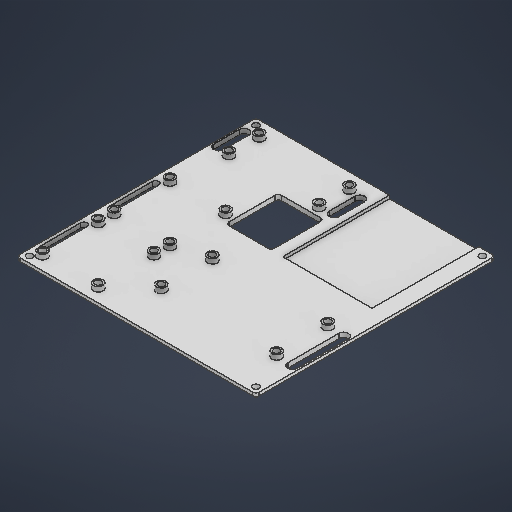
# Autodesk Inventor part: Control Board
Saved by Autodesk Inventor 2026.2 (Build 302298010, 298A)
## iProperties
Created: 2026-04-28
Part Number: Control Board
Material: 일반
Document SubType Name: Modeling
Designer: work
Density: 1 g/cm^3
Appearance: 기본값
Author: work
Autodesk Inventor part; units mm, degrees
ref_plane "YZ Plane" through (0, 0, 0) normal (1, 0, 0) x (0, 1, 0)
ref_plane "XZ Plane" through (0, 0, 0) normal (0, 1, 0) x (-1, 0, 0)
ref_plane "XY Plane" through (0, 0, 0) normal (0, 0, 1) x (1, 0, 0)
sketch "스케치1" plane through (0, 0, 0) normal (0, 1, 0) x (-1, 0, 0)
  line L0 (150, -150) -> (0, -150)
  line L1 (0, -150) -> (0, 0)
  line L2 (0, 0) -> (150, 0)
  line L3 (150, 0) -> (150, -150)
  line L4 (150, -150) -> (0, 0) construction
  line L5 (0, -150) -> (150, 0) construction
  line L6 (4, -4) -> (146, -4) construction
  line L7 (146, -4) -> (146, -146) construction
  line L8 (146, -146) -> (4, -146) construction
  line L9 (4, -146) -> (4, -4) construction
  line L10 (4, -4) -> (146, -146) construction
  line L11 (146, -4) -> (4, -146) construction
  circle A0 centre (146, -4) radius 2
  circle A1 centre (146, -146) radius 2
  circle A2 centre (4, -4) radius 2
  circle A3 centre (4, -146) radius 2
  line L12 (14, -27) -> (86.4, -27) construction
  line L13 (86.4, -27) -> (86.4, -59) construction
  line L14 (86.4, -59) -> (14, -59) construction
  line L15 (14, -59) -> (14, -27) construction
  line L16 (86.4, -43) -> (14, -43) construction
  line L17 (50.2, -27) -> (50.2, -59) construction
  line L18 (10.2, -8) -> (90.2, -8) construction
  line L19 (90.2, -8) -> (90.2, -78) construction
  line L20 (90.2, -78) -> (10.2, -78) construction
  line L21 (10.2, -78) -> (10.2, -8) construction
  line L22 (10.2, -8) -> (90.2, -78) construction
  line L23 (90.2, -8) -> (10.2, -78) construction
  circle A4 centre (14, -27) radius 2
  circle A5 centre (14, -59) radius 2
  circle A6 centre (86.4, -27) radius 2
  circle A7 centre (86.4, -59) radius 2
  line L24 (4, -27) -> (4, -59) construction
  line L25 (1, -27) -> (1, -59)
  line L26 (7, -59) -> (7, -27)
  arc A8 (7, -27) -> (1, -27) centre (4, -27) ccw
  arc A9 (1, -59) -> (7, -59) centre (4, -59) ccw
  line L27 (4, -43) -> (14, -43) construction
  line L28 (10.2, -88) -> (10.2, -78) construction
  circle A10 centre (142, -43) radius 2
  line L29 (142, -8) -> (142, -43) construction
  circle A11 centre (142, -8) radius 2
  line L30 (142, -43) -> (107, -43) construction
  circle A12 centre (107, -43) radius 2
  line L31 (107, -43) -> (107, -8) construction
  line L32 (107, -8) -> (142, -43) construction
  line L33 (142, -8) -> (107, -43) construction
  line L34 (107, -8) -> (142, -8) construction
  circle A13 centre (107, -8) radius 2
  circle A14 centre (142, -88) radius 2
  line L35 (142, -53) -> (142, -88) construction
  circle A15 centre (142, -53) radius 2
  line L36 (142, -88) -> (107, -88) construction
  circle A16 centre (107, -88) radius 2
  line L37 (107, -88) -> (107, -53) construction
  line L38 (107, -53) -> (142, -88) construction
  line L39 (142, -53) -> (107, -88) construction
  line L40 (107, -53) -> (142, -53) construction
  circle A17 centre (107, -53) radius 2
  line L41 (138, -140) -> (81.4, -140) construction
  line L42 (81.4, -140) -> (81.4, -121) construction
  line L43 (81.4, -121) -> (138, -121) construction
  line L44 (138, -121) -> (138, -140) construction
  line L45 (138, -140) -> (81.4, -121) construction
  line L46 (81.4, -140) -> (138, -121) construction
  circle A18 centre (81.4, -121) radius 2
  circle A19 centre (81.4, -140) radius 2
  circle A20 centre (138, -121) radius 2
  circle A21 centre (138, -140) radius 2
  line L47 (73.4, -138.5) -> (73.4, -122.5) construction
  line L48 (76.4, -138.5) -> (76.4, -122.5)
  arc A22 (70.4, -138.5) -> (76.4, -138.5) centre (73.4, -138.5) ccw
  arc A23 (76.4, -122.5) -> (70.4, -122.5) centre (73.4, -122.5) ccw
  line L49 (109.7, -121) -> (109.7, -140) construction
  line L50 (109.7, -130.5) -> (73.4, -130.5) construction
  arc A24 (143, -138.5) -> (149, -138.5) centre (146, -138.5) ccw
  line L51 (143, -138.5) -> (143, -122.5)
  arc A25 (149, -122.5) -> (143, -122.5) centre (146, -122.5) ccw
  line L52 (109.7, -130.5) -> (146, -130.5) construction
  line L53 (146, -138.5) -> (146, -122.5) construction
  line L54 (70.4, -122.5) -> (70.4, -138.5)
  line L55 (149, -122.5) -> (149, -138.5)
  line L56 (66.2, -83) -> (10.2, -83)
  line L57 (10.2, -83) -> (10.2, -166)
  line L58 (10.2, -166) -> (66.2, -166)
  line L59 (66.2, -166) -> (66.2, -83)
  line L60 (102, -83) -> (73.4, -83)
  line L61 (73.4, -83) -> (73.4, -116)
  line L62 (73.4, -116) -> (102, -116)
  line L63 (102, -116) -> (102, -83)
  line L64 (146, -13) -> (146, -38) construction
  line L65 (144, -13) -> (144, -38)
  line L66 (148, -38) -> (148, -13)
  arc A26 (148, -13) -> (144, -13) centre (146, -13) ccw
  arc A27 (144, -38) -> (148, -38) centre (146, -38) ccw
  line L67 (144, -58) -> (144, -83)
  line L68 (148, -83) -> (148, -58)
  arc A28 (148, -58) -> (144, -58) centre (146, -58) ccw
  arc A29 (144, -83) -> (148, -83) centre (146, -83) ccw
  line L69 (146, -58) -> (146, -83) construction
  point P0 (75, -75)
  point P1 (50.2, -43)
  point P2 (124.5, -25.5)
  point P3 (124.5, -70.5)
  point P4 (146, -25.5)
  point P5 (146, -70.5)
  point P6 (10.2, -150)
  point P7 (66.2, -150)
  dimension "d0" = 150
  dimension "d1" = 150
  dimension "d2" = 4
  dimension "d3" = 4
  dimension "d4" = 4
  dimension "d5" = 4
  dimension "d6" = 4
  dimension "d10" = 72.4
  dimension "d11" = 32
  dimension "d12" = 80
  dimension "d13" = 70
  dimension "d14" = 4
  dimension "d15" = 4
  dimension "d16" = 4
  dimension "d17" = 4
  dimension "d18" = 6
  dimension "d19" = 10
  dimension "d20" = 32
  dimension "d21" = 4
  dimension "d22" = 35
  dimension "d23" = 35
  dimension "d24" = 4
  dimension "d25" = 4
  dimension "d26" = 4
  dimension "d27" = 4
  dimension "d28" = 35
  dimension "d29" = 35
  dimension "d30" = 4
  dimension "d31" = 4
  dimension "d32" = 4
  dimension "d33" = 4
  dimension "d34" = 10
  dimension "d37" = 56.6
  dimension "d38" = 19
  dimension "d39" = 4
  dimension "d40" = 4
  dimension "d41" = 4
  dimension "d42" = 4
  dimension "d43" = 16
  dimension "d44" = 8
  dimension "d45" = 3
  dimension "d46" = 6
  dimension "d47" = 56
  dimension "d48" = 83
  dimension "d49" = 5
  dimension "d50" = 5
  dimension "d51" = 5
  dimension "d52" = 25
  dimension "d53" = 2
  dimension "d54" = 25
  dimension "d55" = 2
  constraints: 148 end point, 30 centre point, 25 midpoint, 22 parallel, 21 coincident, 20 point on circle, 16 tangent, 11 perpendicular, 9 horizontal, 7 point on line, 7 symmetric about line, 5 collinear, 3 vertical, 2 other
  measures "d0" distance of L1.end L2.end
  measures "d1" distance of L0.end L1.end
  measures "d2" distance between parallel lines of L3 L7
  measures "d3" diameter of A0
  measures "d4" diameter of A1
  measures "d5" diameter of A2
  measures "d6" diameter of A3
  measures "d10" distance of L12.start L12.end
  measures "d11" distance of L15.start L12.start
  measures "d12" distance of L20.start L28.end
  measures "d13" distance of L23.start L20.start
  measures "d14" diameter of A4
  measures "d15" diameter of A5
  measures "d16" diameter of A6
  measures "d17" diameter of A7
  measures "d18" diameter of A9
  measures "d19" distance from line of L12.start L24
  measures "d20" distance of L24.start L24.end
  measures "d21" vertical distance of L6.start L21.end
  measures "d22" distance of L32.end L30.end
  measures "d23" distance of L34.end L32.end
  measures "d24" diameter of A11
  measures "d25" diameter of A10
  measures "d26" diameter of A13
  measures "d27" diameter of A12
  measures "d28" distance of L38.end L36.end
  measures "d29" distance of L40.end L38.end
  measures "d30" diameter of A15
  measures "d31" diameter of A14
  measures "d32" diameter of A17
  measures "d33" diameter of A16
  measures "d34" distance of A15.centre L32.end
  measures "d37" distance of L42.end L44.start
  measures "d38" distance of L41.end L42.end
  measures "d39" diameter of A18
  measures "d40" diameter of A19
  measures "d41" diameter of A20
  measures "d42" diameter of A21
  measures "d43" distance of L47.start L47.end
  measures "d44" distance between parallel lines of L42 L47
  measures "d45" radius of A22
  measures "d46" vertical distance of L7.end L44.end
  measures "d47" distance of L58.end L57.end
  measures "d48" distance of L57.end L56.end
  measures "d49" distance between parallel lines of L20 L56
  measures "d50" distance between parallel lines of L43 L62
  measures "d51" distance between parallel lines of L37 L63
  measures "d52" distance of L66.start L66.end
  measures "d53" radius of A27
  measures "d54" distance of L68.start L68.end
  measures "d55" radius of A29
extrude "돌출1" add sketch "스케치1" along normal blind 3 contours L0 L59 L56 L57 L1 L2 L3
extrude "돌출2" add sketch "스케치1" along normal blind 1 contours L0 L57 L56 L59
sketch "스케치2" plane through (0, 3, 0) normal (0, 1, 0) x (1, 0, 0)
  line L0 (-150, 0) -> (0, 0) construction
  line L1 (0, 0) -> (0, 150) construction
  line L2 (0, 150) -> (-10.2, 150) construction
  line L3 (-10.2, 150) -> (-10.2, 83) construction
  line L4 (-10.2, 83) -> (-66.2, 83) construction
  line L5 (-66.2, 83) -> (-66.2, 150) construction
  line L6 (-66.2, 150) -> (-150, 150) construction
  line L7 (-150, 150) -> (-150, 0) construction
  circle A0 centre (-81.4, 140) radius 2 construction
  circle A1 centre (-138, 121) radius 2 construction
  circle A2 centre (-107, 88) radius 2 construction
  circle A3 centre (-142, 88) radius 2 construction
  circle A4 centre (-107, 43) radius 2 construction
  circle A5 centre (-142, 43) radius 2 construction
  circle A6 centre (-146, 146) radius 2 construction
  circle A7 centre (-4, 4) radius 2 construction
  circle A8 centre (-4, 146) radius 2 construction
  circle A9 centre (-86.4, 59) radius 2 construction
  circle A10 centre (-14, 59) radius 2 construction
  circle A11 centre (-86.4, 27) radius 2 construction
  circle A12 centre (-14, 27) radius 2 construction
  circle A13 centre (-107, 8) radius 2 construction
  circle A14 centre (-142, 53) radius 2 construction
  circle A15 centre (-107, 53) radius 2 construction
  circle A16 centre (-138, 140) radius 2 construction
  circle A17 centre (-81.4, 121) radius 2 construction
  arc A18 (-148, 58) -> (-144, 58) centre (-146, 58) ccw construction
  line L8 (-148, 58) -> (-148, 83) construction
  arc A19 (-144, 83) -> (-148, 83) centre (-146, 83) ccw construction
  line L9 (-144, 83) -> (-144, 58) construction
  arc A20 (-148, 13) -> (-144, 13) centre (-146, 13) ccw construction
  line L10 (-148, 13) -> (-148, 38) construction
  arc A21 (-144, 38) -> (-148, 38) centre (-146, 38) ccw construction
  line L11 (-144, 38) -> (-144, 13) construction
  line L12 (-102, 83) -> (-102, 116) construction
  line L13 (-102, 116) -> (-73.4, 116) construction
  line L14 (-73.4, 116) -> (-73.4, 83) construction
  line L15 (-73.4, 83) -> (-102, 83) construction
  arc A22 (-70.4, 138.5) -> (-76.4, 138.5) centre (-73.4, 138.5) ccw construction
  line L16 (-70.4, 138.5) -> (-70.4, 122.5) construction
  arc A23 (-76.4, 122.5) -> (-70.4, 122.5) centre (-73.4, 122.5) ccw construction
  line L17 (-76.4, 122.5) -> (-76.4, 138.5) construction
  line L18 (-149, 122.5) -> (-149, 138.5) construction
  arc A24 (-143, 138.5) -> (-149, 138.5) centre (-146, 138.5) ccw construction
  line L19 (-143, 138.5) -> (-143, 122.5) construction
  arc A25 (-149, 122.5) -> (-143, 122.5) centre (-146, 122.5) ccw construction
  circle A26 centre (-142, 8) radius 2 construction
  arc A27 (-1, 59) -> (-7, 59) centre (-4, 59) ccw construction
  line L20 (-1, 59) -> (-1, 27) construction
  arc A28 (-7, 27) -> (-1, 27) centre (-4, 27) ccw construction
  line L21 (-7, 27) -> (-7, 59) construction
  circle A29 centre (-146, 4) radius 2 construction
  circle A30 centre (-142, 8) radius 3
  circle A31 centre (-142, 43) radius 3
  circle A32 centre (-142, 53) radius 3
  circle A33 centre (-142, 88) radius 3
  circle A34 centre (-142, 8) radius 2
  circle A35 centre (-142, 43) radius 2
  circle A36 centre (-142, 53) radius 2
  circle A37 centre (-142, 88) radius 2
  circle A38 centre (-107, 88) radius 3
  circle A39 centre (-107, 88) radius 2
  circle A40 centre (-107, 53) radius 3
  circle A41 centre (-107, 53) radius 2
  circle A42 centre (-107, 43) radius 3
  circle A43 centre (-107, 43) radius 2
  circle A44 centre (-107, 8) radius 3
  circle A45 centre (-107, 8) radius 2
  circle A46 centre (-86.4, 27) radius 3
  circle A47 centre (-86.4, 27) radius 2
  circle A48 centre (-86.4, 59) radius 3
  circle A49 centre (-86.4, 59) radius 2
  circle A50 centre (-14, 27) radius 3
  circle A51 centre (-14, 27) radius 2
  circle A52 centre (-14, 59) radius 3
  circle A53 centre (-14, 59) radius 2
  circle A54 centre (-81.4, 121) radius 3
  circle A55 centre (-81.4, 121) radius 2
  circle A56 centre (-81.4, 140) radius 3
  circle A57 centre (-81.4, 140) radius 2
  circle A58 centre (-138, 121) radius 3
  circle A59 centre (-138, 121) radius 2
  circle A60 centre (-138, 140) radius 3
  circle A61 centre (-138, 140) radius 2
  dimension "d60" = 6
  dimension "d61" = 6
  dimension "d62" = 6
  dimension "d63" = 6
  dimension "d64" = 4
  dimension "d65" = 4
  dimension "d66" = 4
  dimension "d67" = 4
  dimension "d68" = 6
  dimension "d69" = 4
  dimension "d70" = 6
  dimension "d71" = 4
  dimension "d72" = 6
  dimension "d73" = 4
  dimension "d74" = 6
  dimension "d75" = 4
  dimension "d76" = 6
  dimension "d77" = 4
  dimension "d78" = 6
  dimension "d79" = 4
  dimension "d80" = 6
  dimension "d81" = 4
  dimension "d82" = 6
  dimension "d83" = 4
  dimension "d84" = 6
  dimension "d85" = 4
  dimension "d86" = 6
  dimension "d87" = 4
  dimension "d88" = 6
  dimension "d89" = 4
  dimension "d90" = 6
  dimension "d91" = 4
  constraints: 32 centre point, 20 coincident
  measures "d60" diameter of A30
  measures "d61" diameter of A31
  measures "d62" diameter of A32
  measures "d63" diameter of A33
  measures "d64" diameter of A34
  measures "d65" diameter of A35
  measures "d66" diameter of A36
  measures "d67" diameter of A37
  measures "d68" diameter of A38
  measures "d69" diameter of A39
  measures "d70" diameter of A40
  measures "d71" diameter of A41
  measures "d72" diameter of A42
  measures "d73" diameter of A43
  measures "d74" diameter of A44
  measures "d75" diameter of A45
  measures "d76" diameter of A46
  measures "d77" diameter of A47
  measures "d78" diameter of A48
  measures "d79" diameter of A49
  measures "d80" diameter of A50
  measures "d81" diameter of A51
  measures "d82" diameter of A52
  measures "d83" diameter of A53
  measures "d84" diameter of A54
  measures "d85" diameter of A55
  measures "d86" diameter of A56
  measures "d87" diameter of A57
  measures "d88" diameter of A58
  measures "d89" diameter of A59
  measures "d90" diameter of A60
  measures "d91" diameter of A61
extrude "돌출3" add sketch "스케치2" along normal blind 3
fillet "모깎기1" radius 2 8 edges at (0, 1.5, 0) (0, 1.5, -150) (-150, 1.5, 0) (-150, 1.5, -150) (-102, 1.5, -83) (-102, 1.5, -116) (-73.4, 1.5, -116) (-73.4, 1.5, -83)
chamfer "모따기1" distance 1 angle 45 8 edges at (0, 0, -75) (-0.5858, 0, -149.4142) (-75, 0, -150) (-149.4142, 0, -149.4142) (-150, 0, -75) (-149.4142, 0, -0.5858) (-75, 0, 0) (-0.5858, 0, -0.5858)
